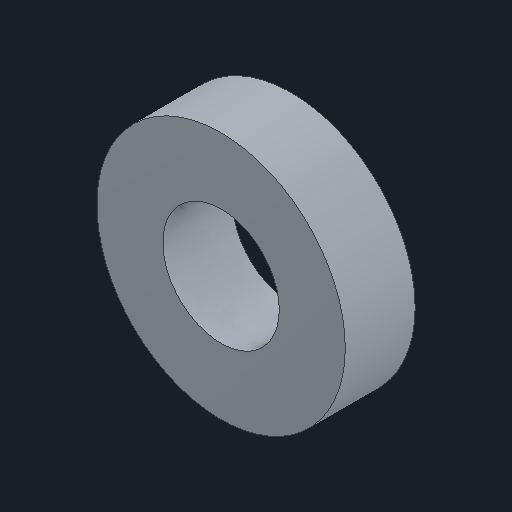
# Autodesk Inventor part: Rolamento_6002
Saved by Autodesk Inventor 2027 (Build 310192000, 192)
## iProperties
Created: 2026-11-10
Part Number: Rolamento_6002
Material: Genérico
Description: Rolamento 6002
Document SubType Name: Modeling
Designer: Bruno Madela
Mass: 5.6478 g
Surface Area: 25.8396 cm^2
Volume: 5.6478 cm^3
Density: 1 g/cm^3
Appearance: Aço
Author: Bruno Madela
Autodesk Inventor part; units mm, degrees
ref_plane "YZ Plane" through (0, 0, 0) normal (1, 0, 0) x (0, 1, 0)
ref_plane "XZ Plane" through (0, 0, 0) normal (0, 1, 0) x (-1, 0, 0)
ref_plane "XY Plane" through (0, 0, 0) normal (0, 0, 1) x (1, 0, 0)
sketch "Esboço1" plane through (0, 0, 0) normal (0, 0, 1) x (1, 0, 0)
  circle A0 centre (0, 0) radius 16
  circle A1 centre (0, 0) radius 7.5
  dimension "d0" = 32
  dimension "d1" = 15
  constraints: 2 centre point
  measures "d0" diameter of A0
  measures "d1" diameter of A1
extrude "Extrusão1" add sketch "Esboço1" along normal blind 9
equation "\"d0\" = diam_externo"
equation "\"d1\" = diam_interno"
equation "\"d2\" = largura"
equation "\"diam_interno\" = 15"
equation "\"diam_externo\" = 32"
equation "\"largura\" = 9"
